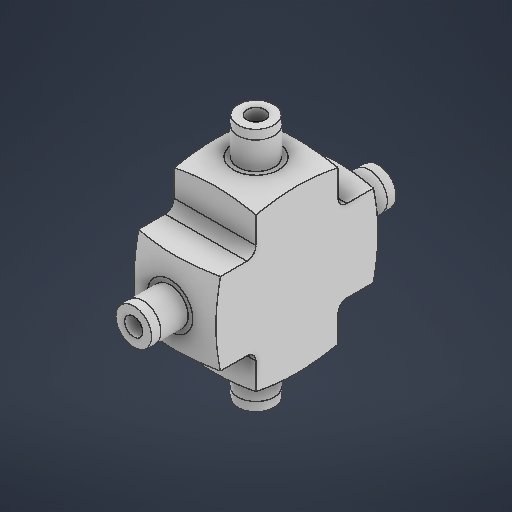
# Autodesk Inventor part: B_v2
Saved by Autodesk Inventor 2026.2 (Build 302298010, 298A)
## iProperties
Created: 2026-03-20
Part Number: B_v2
Material: 일반
Document SubType Name: Modeling
Designer: work
Density: 1 g/cm^3
Appearance: 기본값
Author: work
Autodesk Inventor part; units mm, degrees
ref_plane "YZ Plane" through (0, 0, 0) normal (1, 0, 0) x (0, 1, 0)
ref_plane "XZ Plane" through (0, 0, 0) normal (0, 1, 0) x (-1, 0, 0)
ref_plane "XY Plane" through (0, 0, 0) normal (0, 0, 1) x (1, 0, 0)
sketch "스케치1" plane through (0, 0, 0) normal (0, 1, 0) x (-1, 0, 0)
  line L0 (9, 0) -> (-9, 0)
  line L1 (-9, 0) -> (-9, -18.9)
  line L2 (-9, -18.9) -> (9, -18.9)
  line L3 (9, -18.9) -> (9, 0)
  point P0 (0, 0)
  point P1 (0, 0)
  point P2 (-9, -9.45)
  point P3 (9, -9.45)
  dimension "d0" = 18
  dimension "d1" = 18.9
  constraints: 8 end point, 3 midpoint, 2 parallel, 1 coincident, 1 horizontal, 1 perpendicular
  measures "d0" distance of point (-9, -9.45) point (9, -9.45)
  measures "d1" distance from line of point (0, 0) L2
extrude "돌출1" add sketch "스케치1" along normal mid plane 18
sketch "스케치2" plane through (0, 0, 0) normal (0, 1, 0) x (-1, 0, 0)
  line L0 (-9, -18.9) -> (9, -18.9) projected
  line L1 (0, -18.9) -> (0, -26.9)
  line L2 (0, -26.9) -> (4, -26.9)
  line L3 (4, -26.9) -> (4, -18.9)
  line L4 (2, -11.5844) -> (2, -26.9)
  line L5 (-9, -18.9) -> (-9, 0) projected
  line L6 (-9, 0) -> (9, 0) projected
  line L7 (9, 0) -> (9, -18.9) projected
  line L8 (9, -18.9) -> (-9, -18.9) projected
  line L9 (4, -18.9) -> (9, -17.5603)
  point P0 (0, 0)
  point P1 (2, -26.9)
  point P2 (2, -18.9)
  dimension "d4" = 4
  dimension "d5" = 8
  dimension "d6" = 8
  dimension "d7" = 15
  constraints: 10 end point, 3 midpoint, 3 perpendicular, 2 point on line, 1 vertical
  measures "d4" diameter of L4 L1
  measures "d5" distance from line of L0 point (2, -26.9)
  measures "d6" diameter of L3 L1
  measures "d7" angle of L0 L9
revolve "회전1" add sketch "스케치2" angle 360 about axis through (0, 0, -18.9) along (0, 0, -1) contours L0 L3 L2 L4
sketch "스케치3" plane through (0, 0, 0) normal (0, 1, 0) x (-1, 0, 0)
  line L0 (9, -18.9) -> (-9, -18.9) projected
  line L1 (21.4856, -14.4827) -> (21.4856, -18.9)
  line L2 (21.4856, -18.9) -> (0, -18.9)
  line L3 (0, -18.9) -> (0, -44.814)
  line L4 (-9, -18.9) -> (-9, 0) projected
  line L5 (-9, 0) -> (9, 0) projected
  line L6 (9, 0) -> (9, -18.9) projected
  line L7 (9, -18.9) -> (-9, -18.9) projected
  line L8 (4, -18.9) -> (-4, -18.9) projected
  line L9 (-4, -26.9) -> (4, -26.9) projected
  line L10 (5, -18.9) -> (21.4856, -14.4827)
  point P0 (0, 0)
  point P1 (5, -18.9)
  point P2 (9, -18.9)
  dimension "d10" = 15
  dimension "d11" = 1
  constraints: 8 end point, 2 vertical, 1 collinear, 1 midpoint, 1 point on line
  measures "d10" angle of L2 L10
  measures "d11" distance of L8.start L10.start
revolve "회전2" cut sketch "스케치3" angle 360 about axis through (0, 0, -18.9) along (0, 0, -1) contours L6 L10 L1 L2 | L0 L10 L6
chamfer "모따기1" distance 2 angle 1.5 1 edges at (4, 0, -26.9) measured on face at (-3.987, -0.3219, -24.2333)
pattern_circular "원형 패턴1" count 4 over 360 about axis through (-10, 0, 0) along (1, 0, 0) of "돌출1", "회전1", "회전2", "모따기1"
fillet "모깎기1" radius 2 3 edges at (0, -9, 9) (0, 9, 9) (0, 9, -9)
